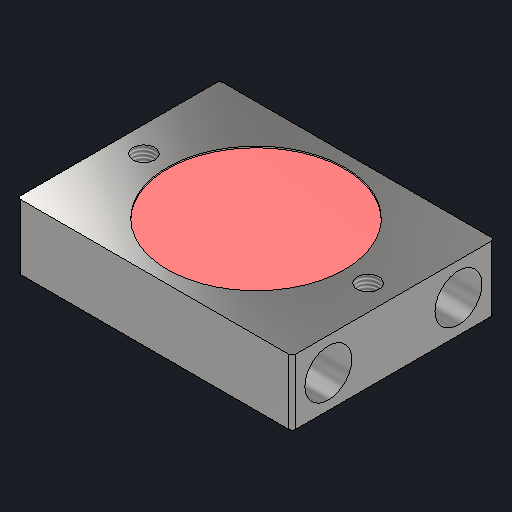
# Autodesk Inventor part: sample-holder-base-hayashi
Saved by Autodesk Inventor 2027.1 (Build 311270010, 270A)
## iProperties
Created: 2025-06-20
Part Number: sample-holder-base-hayashi
Material: ステンレス鋼
Document SubType Name: Modeling
Designer: jin20
Density: 8 g/cm^3
Appearance: 半つや出し
Author: jin20
Autodesk Inventor part; units mm, degrees
ref_plane "YZ Plane" through (0, 0, 0) normal (1, 0, 0) x (0, 1, 0)
ref_plane "XZ Plane" through (0, 0, 0) normal (0, 1, 0) x (-1, 0, 0)
ref_plane "XY Plane" through (0, 0, 0) normal (0, 0, 1) x (1, 0, 0)
sketch "スケッチ1" plane through (0, 0, 0) normal (0, 1, 0) x (-1, 0, 0)
  line L0 (19, -14) -> (-19, -14)
  line L1 (-19, -14) -> (-19, 14)
  line L2 (-19, 14) -> (19, 14)
  line L3 (19, 14) -> (19, -14)
  line L4 (19, -14) -> (-19, 14) construction
  line L5 (-19, -14) -> (19, 14) construction
  point P0 (0, 0)
  dimension "d3" = 38
  dimension "d4" = 28
  constraints: 12 end point, 2 midpoint, 2 parallel, 1 horizontal, 1 perpendicular
  measures "d3" distance of L1.end L2.end
  measures "d4" distance of L0.end L1.end
extrude "押し出し1" add sketch "スケッチ1" along normal blind 9
sketch "スケッチ2" plane through (19, 0, 14) normal (1, 0, 0) x (0, 0, -1)
  line L0 (14, 0) -> (14, 4.5) construction
  line L1 (14, 4.5) -> (23, 4.5) construction
  circle A0 centre (23, 4.5) radius 3.25
  circle A1 centre (5, 4.5) radius 3.25
  dimension "d5" = 4.5
  dimension "d6" = 9
  dimension "d7" = 6.5
  constraints: 4 end point, 2 centre point, 1 coincident, 1 perpendicular, 1 symmetric about line, 1 vertical, 1 other
  measures "d5" distance of L0.start L0.end
  measures "d6" distance of L0.end L1.end
  measures "d7" diameter of A0
extrude "押し出し2" cut sketch "スケッチ2" against normal through all
sketch "スケッチ3" plane through (0, 9, 0) normal (0, 1, 0) x (1, 0, 0)
  circle A0 centre (0, 0) radius 12.25
  dimension "d10" = 24.5
  constraints: 1 centre point, 1 coincident
  measures "d10" diameter of A0
extrude "押し出し3" cut sketch "スケッチ3" against normal blind 0.2
sketch "スケッチ4" plane through (0, 9, 0) normal (0, 1, 0) x (1, 0, 0)
  line L0 (0, 0) -> (15.5, 0) construction
  circle A0 centre (15.5, 0) radius 1.5
  line L1 (0, 0) -> (0, -14) construction
  line L2 (-19, -14) -> (19, -14) projected
  circle A1 centre (-15.5, 0) radius 1.5
  dimension "d13" = 15.5
  dimension "d14" = 3
  constraints: 4 end point, 2 centre point, 1 coincident, 1 horizontal, 1 midpoint, 1 symmetric about line, 1 other
  measures "d13" distance of L0.start L0.end
  measures "d14" diameter of A0
extrude "押し出し4" cut sketch "スケッチ4" against normal through all
fillet "フィレット1" radius 0.5 4 edges at (19, 4.5, 14) (19, 4.5, -14) (-19, 4.5, -14) (-19, 4.5, 14)
thread "ねじ1" size "M3x0.5" class "6H" standard "ANSI Metric M Profile" full length
thread "ねじ2" size "M3x0.5" class "6H" standard "ANSI Metric M Profile" full length
